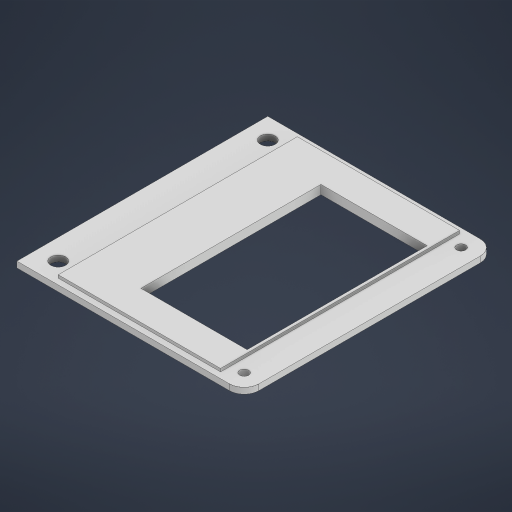
# Autodesk Inventor part: КРЫШКА верхней основы
Saved by Autodesk Inventor 2024 (Build 280153000, 153)
## iProperties
Created: 2026-05-29
Part Number: КРЫШКА верхней основы
Material: Типовые
Document SubType Name: Modeling
Designer: mitm
Density: 1 g/cm^3
Appearance: По умолчанию
Author: mitm
Autodesk Inventor part; units mm, degrees
ref_plane "YZ Plane" through (0, 0, 0) normal (1, 0, 0) x (0, 1, 0)
ref_plane "XZ Plane" through (0, 0, 0) normal (0, 1, 0) x (-1, 0, 0)
ref_plane "XY Plane" through (0, 0, 0) normal (0, 0, 1) x (1, 0, 0)
sketch "Эскиз1" plane through (0, 0, 0) normal (0, 1, 0) x (-1, 0, 0)
  line L0 (19.7795, 40.5) -> (-19.7795, 40.5)
  line L1 (-19.7795, -40.5) -> (19.7795, -40.5)
  line L2 (27.5, 42.5) -> (-27.5, 42.5)
  line L3 (-27.5, -42.5) -> (27.5, -42.5)
  line L4 (-27.5, -42.5) -> (-44.5, -42.5)
  line L5 (-49.5, -37.5) -> (-49.5, 37.5)
  line L6 (-44.5, 42.5) -> (-27.5, 42.5)
  line L7 (-47.5, -33) -> (-47.5, 33)
  line L8 (-27.5, 40.5) -> (-42.5, 40.5)
  line L9 (-47.5, 35.5) -> (-47.5, 33)
  line L10 (-27.5, -40.5) -> (-42.5, -40.5)
  line L11 (-47.5, -35.5) -> (-47.5, -33)
  circle A0 centre (-43.75, 36.75) radius 1.5
  circle A1 centre (-43.75, -36.75) radius 1.5
  arc A2 (-42.5, 40.5) -> (-47.5, 35.5) centre (-42.5, 35.5) ccw
  arc A3 (-44.5, 42.5) -> (-49.5, 37.5) centre (-44.5, 37.5) ccw
  arc A4 (-47.5, -35.5) -> (-42.5, -40.5) centre (-42.5, -35.5) ccw
  arc A5 (-49.5, -37.5) -> (-44.5, -42.5) centre (-44.5, -37.5) ccw
  line L12 (25.5, 40.5) -> (-25.5, 40.5)
  line L13 (-25.5, -40.5) -> (25.5, -40.5)
  line L14 (-27.5, 40.5) -> (-35, 40.5)
  line L15 (-47.5, 33) -> (-43.5, 33)
  line L16 (-37.5, 40.5) -> (-33.5, 40.5)
  line L17 (-37.5, 40.5) -> (-41.5, 40.5)
  line L18 (-41.5, 40.5) -> (-41.5, 35)
  arc A6 (-43.5, 33) -> (-41.5, 35) centre (-43.5, 35) ccw
  line L19 (-37.5, -40.5) -> (-33.5, -40.5)
  line L20 (-33.5, -40.5) -> (-41.5, -40.5)
  line L21 (-41.5, -40.5) -> (-41.5, -35)
  line L22 (-43.5, -33) -> (-47.5, -33)
  arc A7 (-41.5, -35) -> (-43.5, -33) centre (-43.5, -35) ccw
  line L23 (-27.5, 40.5) -> (-25.5, 40.5)
  line L24 (-25.5, -40.5) -> (-27.5, -40.5)
  line L25 (-41.5, -40.5) -> (13.5, -40.5)
  line L26 (13.5, 40.5) -> (-41.5, 40.5)
  line L27 (-41.5, 40.5) -> (-41.5, -40.5)
  line L28 (27.5, 40.5) -> (25.5, 40.5)
  line L29 (27.5, -40.5) -> (25.5, -40.5)
  line L30 (27.5, 0) -> (27.5, -40.5)
  line L31 (27.5, 0) -> (27.5, 40.5)
  line L32 (27.5, 40.5) -> (27.5, 42.5)
  line L33 (27.5, -40.5) -> (27.5, -42.5)
  line L34 (27.5, 42.5) -> (25.5, 42.5)
  line L35 (25.5, 42.5) -> (25.5, -42.5)
  line L36 (-41.5, 0) -> (-39.5, 0)
  line L37 (-39.5, 0) -> (-39.5, -40.5)
  line L38 (-39.5, 0) -> (-39.5, 40.5)
  line L39 (-39.5, -40.5) -> (15.5, -40.5)
  line L40 (15.5, -40.5) -> (15.5, 40.5)
  circle A8 centre (20.5, 35.5) radius 5
  circle A9 centre (20.5, -35.5) radius 5
  circle A10 centre (20.5, 35.5) radius 2.5
  circle A11 centre (20.5, -35.5) radius 2.5
  line L41 (-39.5, 40.5) -> (15.5, -40.5)
  line L42 (-39.5, -40.5) -> (15.5, 40.5)
  line L43 (-12, 0) -> (-39.5, 0)
  line L44 (-39.5, 40.5) -> (-39.5, 30.5)
  line L45 (-39.5, 30.5) -> (-38.5, 30.5)
  line L46 (-38.5, 30.5) -> (-38.5, -30.5)
  line L47 (-38.5, -30.5) -> (-2.5, -30.5)
  line L48 (-2.5, -30.5) -> (-2.5, 30.5)
  line L49 (-2.5, 30.5) -> (-38.5, 30.5)
  point P0 (0, 0)
  point P1 (-49.5, -42.5)
  point P2 (-47.5, -40.5)
  point P3 (-41.5, -33)
  dimension "d116" = 2
  dimension "d117" = 55
  dimension "d118" = 5
  dimension "d119" = 5
  dimension "d148" = 10
  dimension "d149" = 1
  dimension "d150" = 61
  dimension "d151" = 36
  constraints: 100 end point, 23 point on line, 18 tangent, 12 centre point, 12 perpendicular, 12 point on circle, 8 equal length, 8 horizontal, 3 equal radius, 2 coincident, 2 midpoint, 1 vertical
  measures "d116" distance of L36.start L36.end
  measures "d117" distance of L37.end L39.end
  measures "d118" diameter of A10
  measures "d119" diameter of A11
  measures "d148" distance of L38.end L44.end
  measures "d149" distance of L44.end L45.end
  measures "d150" distance of L45.end L46.end
  measures "d151" distance of L46.end L47.end
extrude "Выдавливание27" add sketch "Эскиз1" against normal blind 2 contours L12 A8 L40 L0 | L0 L12 L23 L8 A2 L9 L7 L11 A4 L10 L24 L13 L1 L35 L3 L4 A5 L5 A3 L6 L2 | L42 L48 L49 L41 L8 L23 L12 L0 | L40 L41 L48 L42 | L12 L35 A8 | A8 | A8 L35 A9 L40 | L35 L2 L32 L28 | L28 L31 L30 L29 L35 | A9 L13 L1 L40 | A9 | L41 L1 L13 L24 L10 L42 L47 L48 | L35 L13 A9 | L49 L45 L38 L41 | L42 L37 L43 L46 L47 | L43 L38 L45 L46 | L29 L33 L3 L35 | L38 L36 L27 L18 L8 | L10 L21 L27 L36 L37 | L18 A6 L15 L9 A2 L8 | L10 A4 L11 L22 A7 L21 | L27 A7 L22 L7 L15 A6
extrude "Выдавливание28" add sketch "Эскиз1" along normal blind 1 contours L42 L48 L49 L41 L8 L23 L12 L0 | L40 L41 L48 L42 | L41 L1 L13 L24 L10 L42 L47 L48 | L49 L45 L38 L41 | L42 L37 L43 L46 L47 | L43 L38 L45 L46
